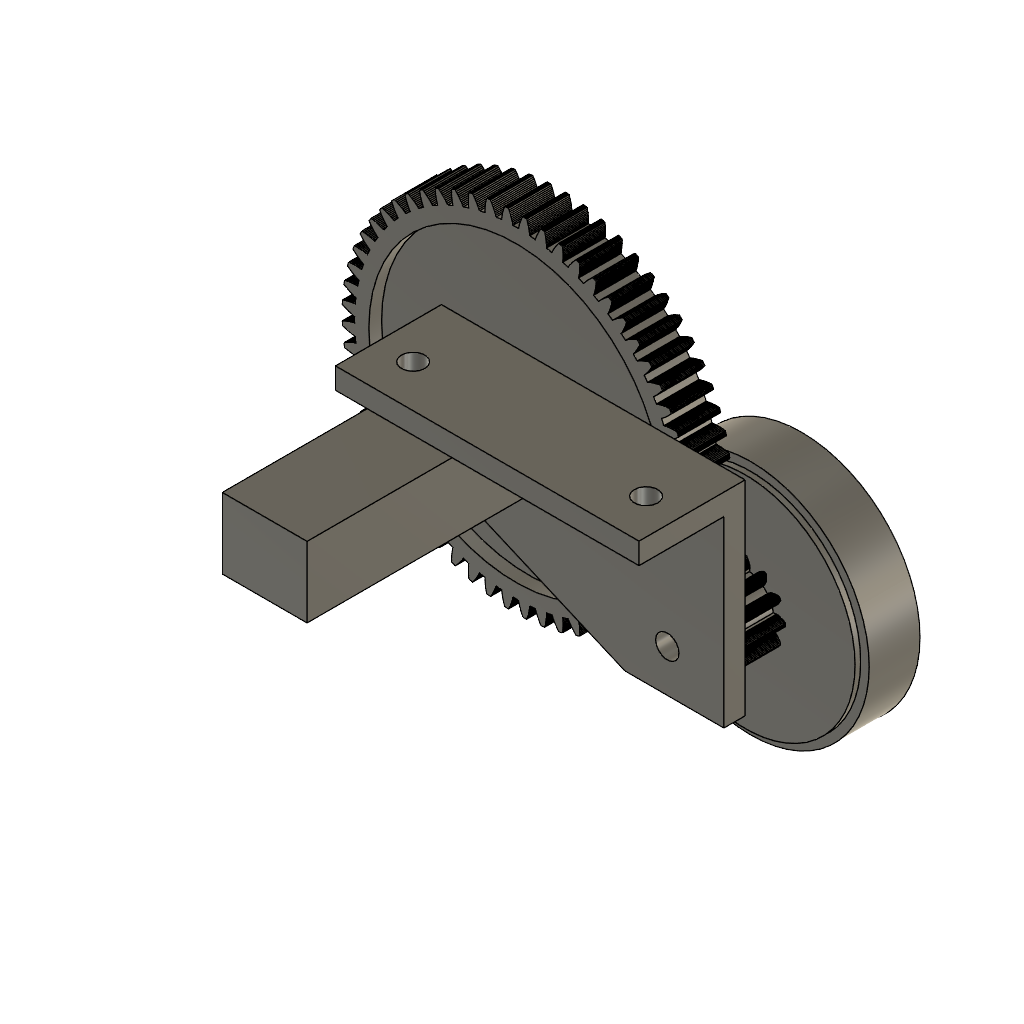
n20_5x_stepup (Autodesk Fusion 360 design; units mm, degrees)
Autodesk Fusion 360 part; units mm, degrees
sketch "gear root" plane through (0, 0, 0) normal (0, 0, 1) x (1, 0, 0) in component "Big gear 60T"
  circle A0 centre (0, 0) radius 22.76
extrude "Extrude1" add sketch "gear root" along normal blind 6 makes body 1 in component "Big gear 60T"
sketch "gear tooth" plane through (0, 0, 0) normal (0, 0, 1) x (1, 0, 0) in component "Big gear 60T"
  line L0 (19.162, 11.5234) -> (19.5048, 11.7295)
  line L1 (19.5048, 11.7295) -> (19.6439, 11.8474)
  line L2 (19.6439, 11.8474) -> (19.7787, 11.9723)
  line L3 (19.7787, 11.9723) -> (19.9099, 12.1031)
  line L4 (19.9099, 12.1031) -> (20.0379, 12.239)
  line L5 (20.0379, 12.239) -> (20.1629, 12.3796)
  line L6 (20.1629, 12.3796) -> (20.285, 12.5246)
  line L7 (20.285, 12.5246) -> (20.4044, 12.6736)
  line L8 (20.4044, 12.6736) -> (20.5212, 12.8266)
  line L9 (20.5212, 12.8266) -> (20.6354, 12.9832)
  line L10 (20.6354, 12.9832) -> (20.7472, 13.1433)
  line L11 (20.7472, 13.1433) -> (20.6728, 13.26)
  line L12 (20.6728, 13.26) -> (20.5977, 13.3763)
  line L13 (20.5977, 13.3763) -> (20.522, 13.4922)
  line L14 (20.522, 13.4922) -> (20.4457, 13.6076)
  line L15 (20.4457, 13.6076) -> (20.2539, 13.5707)
  line L16 (20.2539, 13.5707) -> (20.0644, 13.53)
  line L17 (20.0644, 13.53) -> (19.8772, 13.4855)
  line L18 (19.8772, 13.4855) -> (19.6924, 13.4371)
  line L19 (19.6924, 13.4371) -> (19.5103, 13.3844)
  line L20 (19.5103, 13.3844) -> (19.331, 13.3275)
  line L21 (19.331, 13.3275) -> (19.1548, 13.2659)
  line L22 (19.1548, 13.2659) -> (18.982, 13.1992)
  line L23 (18.982, 13.1992) -> (18.8131, 13.1268)
  line L24 (18.8131, 13.1268) -> (18.6488, 13.0476)
  line L25 (18.6488, 13.0476) -> (18.321, 12.8183)
  line L26 (18.321, 12.8183) -> (19.162, 11.5234)
extrude "Extrude2" add sketch "gear tooth" along normal blind 6 bodies 1 in component "Big gear 60T"
pattern_circular "C-Pattern1" count 60 over 360 about axis through (0, 0, 1.75) along (0, 0, 1) of "Extrude2" in component "Big gear 60T"
sketch "web cut inner" plane through (0, 0, 0) normal (0, 0, 1) x (1, 0, 0) in component "Big gear 60T"
  circle A0 centre (0, 0) radius 20.76
  circle A1 centre (0, 0) radius 5
extrude "Extrude3" cut sketch "web cut inner" along normal blind 1.8 bodies 1 in component "Big gear 60T"
ref_plane "WorkPlane1" through (0, 0, 4.2) normal (0, 0, 1) x (1, 0, 0) in component "Big gear 60T"
sketch "web cut outer" plane through (0, 0, 4.2) normal (0, 0, 1) x (1, 0, 0) in component "Big gear 60T"
  circle A0 centre (0, 0) radius 20.76
  circle A1 centre (0, 0) radius 5
extrude "Extrude4" cut sketch "web cut outer" along normal blind 1.8 bodies 1 in component "Big gear 60T"
sketch "D bore" plane through (0, 0, 0) normal (0, 0, 1) x (1, 0, 0) in component "Big gear 60T"
  circle A0 centre (0, 0) radius 1.575
  line L0 (0.975, -1.5369) -> (0.975, 1.5369)
extrude "Extrude5" cut sketch "D bore" along normal mid plane 200 contours A0 L0 picked at (0.4016, -0.5114) bodies 1 in component "Big gear 60T"
sketch "pinion root" plane through (0, 0, 0) normal (0, 0, 1) x (1, 0, 0) in component "Pinion wheel 12T"
  circle A0 centre (0, 0) radius 4.04
extrude "Extrude1'" add sketch "pinion root" along normal blind 7.5 separate body makes body 2 in component "Pinion wheel 12T"
sketch "pinion tooth" plane through (0, 0, 0) normal (0, 0, 1) x (1, 0, 0) in component "Pinion wheel 12T"
  line L0 (-3.3937, -1.3163) -> (-4.2053, -1.6311)
  line L1 (-4.2053, -1.6311) -> (-4.3111, -1.6925)
  line L2 (-4.3111, -1.6925) -> (-4.4108, -1.7692)
  line L3 (-4.4108, -1.7692) -> (-4.506, -1.8563)
  line L4 (-4.506, -1.8563) -> (-4.5969, -1.9524)
  line L5 (-4.5969, -1.9524) -> (-4.6837, -2.0565)
  line L6 (-4.6837, -2.0565) -> (-4.7663, -2.168)
  line L7 (-4.7663, -2.168) -> (-4.8448, -2.2864)
  line L8 (-4.8448, -2.2864) -> (-4.9189, -2.4113)
  line L9 (-4.9189, -2.4113) -> (-4.9885, -2.5424)
  line L10 (-4.9885, -2.5424) -> (-5.0536, -2.6795)
  line L11 (-5.0536, -2.6795) -> (-5.0044, -2.7702)
  line L12 (-5.0044, -2.7702) -> (-4.9537, -2.86)
  line L13 (-4.9537, -2.86) -> (-4.9013, -2.9489)
  line L14 (-4.9013, -2.9489) -> (-4.8473, -3.0367)
  line L15 (-4.8473, -3.0367) -> (-4.6961, -3.049)
  line L16 (-4.6961, -3.049) -> (-4.5477, -3.0542)
  line L17 (-4.5477, -3.0542) -> (-4.4024, -3.0525)
  line L18 (-4.4024, -3.0525) -> (-4.2607, -3.0438)
  line L19 (-4.2607, -3.0438) -> (-4.1228, -3.0279)
  line L20 (-4.1228, -3.0279) -> (-3.9893, -3.0048)
  line L21 (-3.9893, -3.0048) -> (-3.8606, -2.9741)
  line L22 (-3.8606, -2.9741) -> (-3.7376, -2.9353)
  line L23 (-3.7376, -2.9353) -> (-3.6213, -2.8873)
  line L24 (-3.6213, -2.8873) -> (-3.5152, -2.8263)
  line L25 (-3.5152, -2.8263) -> (-2.8368, -2.2808)
  line L26 (-2.8368, -2.2808) -> (-3.3937, -1.3163)
extrude "Extrude2'" add sketch "pinion tooth" along normal blind 7.5 bodies 2 in component "Pinion wheel 12T"
pattern_circular "C-Pattern1'" count 12 over 360 about axis through (0, 0, 1.75) along (0, 0, 1) of "Extrude2'" in component "Pinion wheel 12T"
ref_plane "WorkPlane1" through (0, 0, 7.5) normal (0, 0, 1) x (1, 0, 0) in component "Pinion wheel 12T"
sketch "rim" plane through (0, 0, 7.5) normal (0, 0, 1) x (1, 0, 0) in component "Pinion wheel 12T"
  circle A0 centre (0, 0) radius 14.75
extrude "Extrude3'" add sketch "rim" along normal blind 8.8 bodies 2 in component "Pinion wheel 12T"
ref_plane "WorkPlane2" through (0, 0, 7.5) normal (0, 0, 1) x (1, 0, 0) in component "Pinion wheel 12T"
sketch "lip inner" plane through (0, 0, 7.5) normal (0, 0, 1) x (1, 0, 0) in component "Pinion wheel 12T"
  circle A0 centre (0, 0) radius 15.55
extrude "Extrude4'" add sketch "lip inner" along normal blind 0.8 bodies 2 in component "Pinion wheel 12T"
ref_plane "WorkPlane3" through (0, 0, 15.5) normal (0, 0, 1) x (1, 0, 0) in component "Pinion wheel 12T"
sketch "lip outer" plane through (0, 0, 15.5) normal (0, 0, 1) x (1, 0, 0) in component "Pinion wheel 12T"
  circle A0 centre (0, 0) radius 15.55
extrude "Extrude5'" add sketch "lip outer" along normal blind 0.8 bodies 2 in component "Pinion wheel 12T"
ref_plane "WorkPlane4" through (0, 0, 9.9) normal (0, 0, 1) x (1, 0, 0) in component "Pinion wheel 12T"
sketch "wheel pocket" plane through (0, 0, 9.9) normal (0, 0, 1) x (1, 0, 0) in component "Pinion wheel 12T"
  circle A0 centre (0, 0) radius 13.25
  circle A1 centre (0, 0) radius 5.45
extrude "Extrude6" cut sketch "wheel pocket" along normal blind 6.4 bodies 2 in component "Pinion wheel 12T"
sketch "bore" plane through (0, 0, 0) normal (0, 0, 1) x (1, 0, 0) in component "Pinion wheel 12T"
  circle A0 centre (0, 0) radius 2.5
extrude "Extrude7" cut sketch "bore" along normal mid plane 200 bodies 2 in component "Pinion wheel 12T"
ref_plane "WorkPlane5" through (0, 0, 11.3) normal (0, 0, 1) x (1, 0, 0) in component "Pinion wheel 12T"
sketch "bearing pocket" plane through (0, 0, 11.3) normal (0, 0, 1) x (1, 0, 0) in component "Pinion wheel 12T"
  circle A0 centre (0, 0) radius 3.05
extrude "Extrude8" cut sketch "bearing pocket" along normal blind 5 bodies 2 in component "Pinion wheel 12T"
ref_plane "WorkPlane1" through (0, 0, -3) normal (0, 0, 1) x (1, 0, 0) in component "Bracket"
sketch "plate" plane through (0, 0, -3) normal (0, 0, 1) x (1, 0, 0) in component "Bracket"
  line L0 (8, 6) -> (8, -22.9)
  line L1 (8, -22.9) -> (-34.9415, -22.9)
  line L2 (-34.9415, -22.9) -> (-34.9415, -6.4)
  line L3 (-34.9415, -6.4) -> (-6, 6)
  line L4 (-6, 6) -> (8, 6)
extrude "Extrude1''" add sketch "plate" along normal blind 3 separate body makes body 3 in component "Bracket"
ref_plane "WorkPlane2" through (0, 0, -15) normal (0, 0, 1) x (1, 0, 0) in component "Bracket"
sketch "flange" plane through (0, 0, -15) normal (0, 0, 1) x (1, 0, 0) in component "Bracket"
  line L0 (-34.9415, -22.9) -> (8, -22.9)
  line L1 (8, -22.9) -> (8, -19.9)
  line L2 (8, -19.9) -> (-34.9415, -19.9)
  line L3 (-34.9415, -19.9) -> (-34.9415, -22.9)
extrude "Extrude2''" add sketch "flange" along normal blind 15 bodies 3 in component "Bracket"
sketch "plate holes" plane through (0, 0, 0) normal (0, 0, 1) x (1, 0, 0) in component "Bracket"
  circle A0 centre (0, 0) radius 1.65
  circle A1 centre (-24.9415, -14.4) radius 2.3
  circle A2 centre (-29.4415, -14.4) radius 0.9
  circle A3 centre (-20.4415, -14.4) radius 0.9
extrude "Extrude3''" cut sketch "plate holes" along normal mid plane 200 bodies 3 in component "Bracket"
sketch "flange holes" plane through (0, 0, 0) normal (0, 1, 0) x (1, 0, 0) in component "Bracket"
  circle A0 centre (3, 9) radius 1.65
  circle A1 centre (-29.9415, 9) radius 1.65
extrude "Extrude4''" cut sketch "flange holes" along normal mid plane 200 bodies 3 in component "Bracket"
sketch "tube" plane through (0, 0, 0) normal (0, 0, 1) x (1, 0, 0) in component "Spacer B (plate to bearing)"
  circle A0 centre (0, 0) radius 2.1
  circle A1 centre (0, 0) radius 1.65
extrude "Extrude1'''" add sketch "tube" along normal blind 11.8 separate body makes body 4 in component "Spacer B (plate to bearing)"
ref_plane "WorkPlane1" through (0, 0, 16.8) normal (0, 0, 1) x (1, 0, 0) in component "Spacer A (screw head)"
sketch "ring" plane through (0, 0, 16.8) normal (0, 0, 1) x (1, 0, 0) in component "Spacer A (screw head)"
  circle A0 centre (0, 0) radius 2.1
  circle A1 centre (0, 0) radius 1.65
extrude "Extrude1''''" add sketch "ring" along normal blind 1 separate body makes body 5 in component "Spacer A (screw head)"
ref_plane "WorkPlane1" through (0, 0, -35) normal (0, 0, 1) x (1, 0, 0) in component "N20 motor (ref, do not print)"
sketch "body" plane through (0, 0, -35) normal (0, 0, 1) x (1, 0, 0) in component "N20 motor (ref, do not print)"
  line L0 (-6, -5) -> (6, -5)
  line L1 (6, -5) -> (6, 5)
  line L2 (6, 5) -> (-6, 5)
  line L3 (-6, 5) -> (-6, -5)
extrude "Extrude1'''''" add sketch "body" along normal blind 32 separate body makes body 6 in component "N20 motor (ref, do not print)"
ref_plane "WorkPlane2" through (0, 0, -3) normal (0, 0, 1) x (1, 0, 0) in component "N20 motor (ref, do not print)"
sketch "shaft" plane through (0, 0, -3) normal (0, 0, 1) x (1, 0, 0) in component "N20 motor (ref, do not print)"
  circle A0 centre (0, 0) radius 1.5
extrude "Extrude2'''" add sketch "shaft" along normal blind 10 separate body makes body 7 in component "N20 motor (ref, do not print)"
ref_plane "WorkPlane1" through (0, 0, 8.8) normal (0, 0, 1) x (1, 0, 0) in component "Tyre (ref, do not print)"
sketch "tyre" plane through (0, 0, 8.8) normal (0, 0, 1) x (1, 0, 0) in component "Tyre (ref, do not print)"
  circle A0 centre (0, 0) radius 16.75
  circle A1 centre (0, 0) radius 14.75
extrude "Extrude1''''''" add sketch "tyre" along normal blind 7.2 separate body makes body 8 in component "Tyre (ref, do not print)"
component "Big gear 60T" placed x (1, 0, 0) y (0, 0, -1) z (0, 1, 0) at (-24.9415, 0.5, 31.15)
component "Pinion wheel 12T" placed x (1, 0, 0) y (0, 0, -1) z (0, 1, 0) at (0, 0.5, 16.75)
component "Bracket" placed x (1, 0, 0) y (0, 0, -1) z (0, 1, 0) at (0, 0, 16.75)
component "Spacer B (plate to bearing)" placed x (1, 0, 0) y (0, 0, -1) z (0, 1, 0) at (0, 0, 16.75)
component "Spacer A (screw head)" placed x (1, 0, 0) y (0, 0, -1) z (0, 1, 0) at (0, 0, 16.75)
component "N20 motor (ref, do not print)" placed x (1, 0, 0) y (0, 0, -1) z (0, 1, 0) at (-24.9415, 0, 31.15)
component "Tyre (ref, do not print)" placed x (1, 0, 0) y (0, 0, -1) z (0, 1, 0) at (0, 0, 16.75)
